Gate (Autodesk Fusion 360 design; units mm, degrees)
part number: 2026-10-17-15-00-51-170
Autodesk Fusion 360 part; units mm, degrees
sketch "Sketch1" plane through (0, 0, 0) normal (0, 0, 1) x (1, 0, 0)
  line L0 (360, 150) -> (-360, 150)
  line L1 (-360, 150) -> (-360, -150)
  line L2 (-360, -150) -> (360, -150)
  line L3 (360, -150) -> (360, 150)
  line L4 (360, 150) -> (-360, -150) construction
  line L5 (-360, 150) -> (360, -150) construction
  dimension "d1" = 720
  dimension "d2" = 300
  constraint horizontal L0
  constraint perpendicular L0 L1
  constraint parallel L0 L2
  constraint parallel L1 L3
  constraint coincident L4 origin
  constraint coincident L5 origin
  measures "d1" distance of L1.end L2.end
  measures "d2" distance of L0.end L1.end
extrude "Extrude1" add sketch "Sketch1" along normal blind 1
sketch "Sketch2" plane through (0, 0, 1) normal (0, 0, 1) x (-1, 0, 0)
  line L0 (-360, 150) -> (-360, -150)
  line L1 (-360, -150) -> (360, -150)
  line L2 (360, -150) -> (360, 150)
  line L3 (360, 150) -> (-360, 150)
  line L4 (360, -150) -> (300, -150)
  line L5 (300, -150) -> (300, 150)
  line L6 (300, 150) -> (360, 150)
  line L7 (360, 150) -> (360, -150)
  line L8 (0, -150) -> (0, 150) construction
  line L9 (-300, -150) -> (-300, 150)
  line L10 (-360, -150) -> (-300, -150)
  line L11 (-360, 150) -> (-360, -150)
  line L12 (-300, 150) -> (-360, 150)
  constraint horizontal L4
  constraint vertical L5
  constraint horizontal L6
  constraint vertical L7
  constraint coincident L3 L5.end
  constraint coincident L1.end L2.start
  constraint midpoint L1 L8.start
  constraint midpoint L3 L8.end
  constraint symmetric L1.end L8 L0.end
  constraint symmetric L4.end L8 L9.start
  constraint symmetric L5.end L8 L9.end
  constraint symmetric L2.end L8 L0.start
extrude "Extrude2" add sketch "Sketch2" along normal blind 400 contours L0 L1 L3 L9 L10 L11 L12 | L1 L2 L3 L4 L5 L6 L7
equation "d1 = ( ( ( ( 6 * 2 ) * 1 cm ) ) + 60 * 1 cm )"
